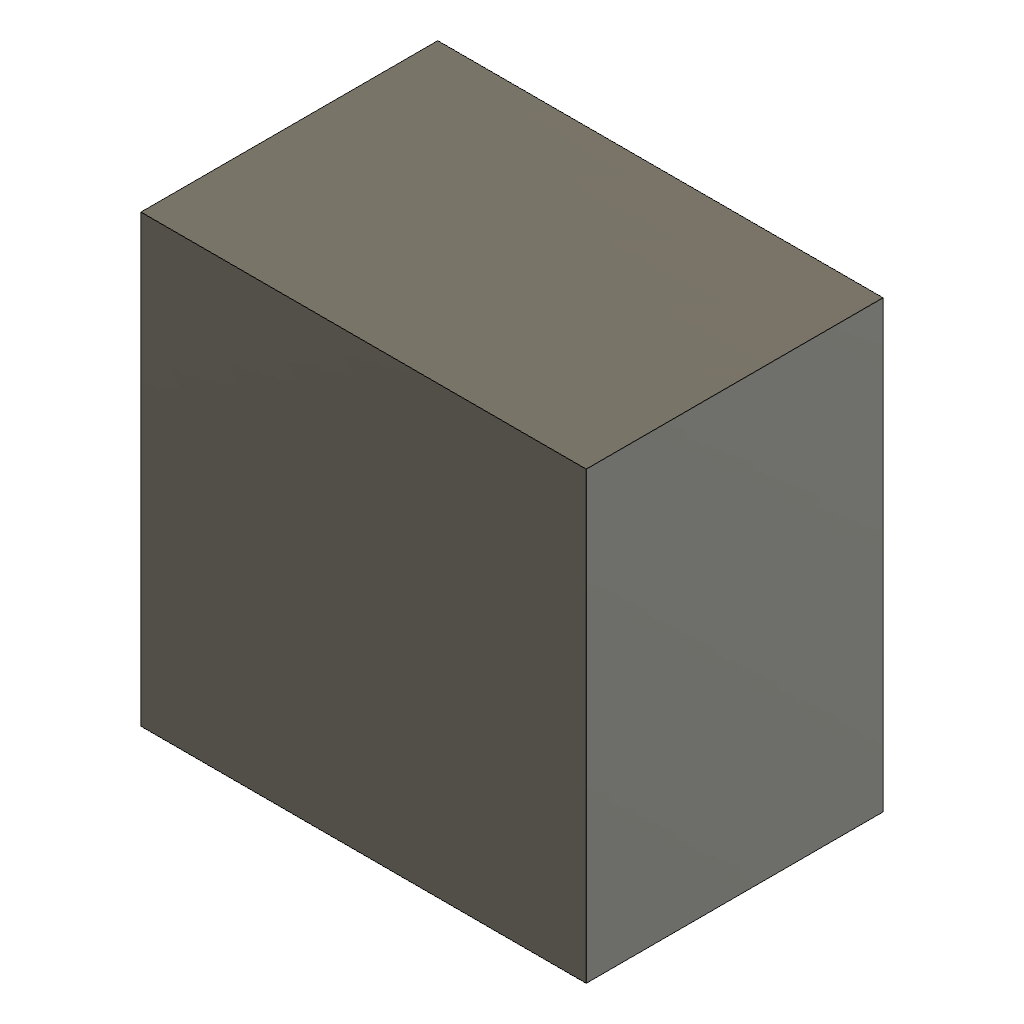
shell_body (Autodesk Fusion 360 design; units mm, degrees)
part number: 2026-10-20-23-25-49-011
Autodesk Fusion 360 part; units mm, degrees
sketch "BodySelectionSeedSketch1" plane through (0, 0, 0) normal (0, 0, 1) x (1, 0, 0)
  line L0 (10, 10) -> (40, 10)
  line L1 (40, 10) -> (40, 40)
  line L2 (40, 40) -> (10, 40)
  line L3 (10, 40) -> (10, 10)
extrude "BodySelectionSeed1" add sketch "BodySelectionSeedSketch1" along normal blind 20
shell "ProbeBodySelection" thickness 1 removed faces 0 bodies 1
named bodies: "SelectedBody1"
